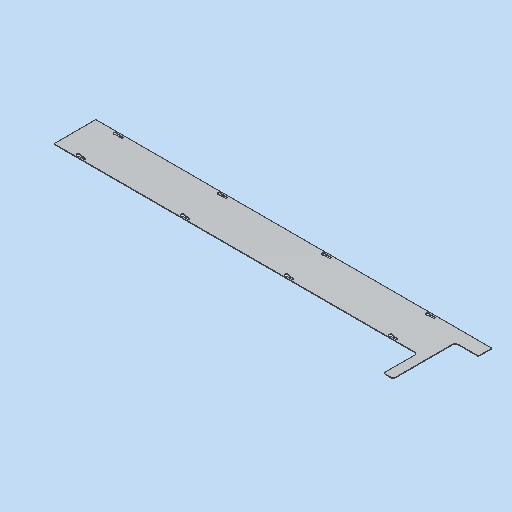
# Autodesk Inventor part: MM0948AN170_G01_102
Saved by Autodesk Inventor 2023.3 (Build 273359000, 359)
## iProperties
Part Number: MM0948AN170_G01_102
Material: 3.3535 AlMg3 - AW 5754 (Blech)
Description: =<RBPARTNOTITLE2>
Document SubType Name: Blech
Designer: Benutzer
Mass: 971.716 g
Surface Area: 3674.69 cm^2
Volume: 360.028 cm^3
Density: 2.699 g/cm^3
Sheet Metal Rule: Standard_mm
Appearance: Aluminium AnP
Vendor: ASW
Created: 2023-03-23
RBCHANGEDESCRIPTION1: Erstfreigabe
RBCHANGENO1: 00
RBDOCUMENTTYPE: DRF
RBDOCUMENTVERSION: 00
RBDRAWINGMAINSCALE: 1:1
RBDRAWINGMISSINGSPEC: --
RBDRAWINGVOLUME: --
RBDSV1: 0850
RBGBDETAILS: 43274
RBGBEDGESIN1: +0,5
RBGBEDGESIN2: +0,2
RBGBEDGESOUT1: -0,3
RBGBEDGESOUT2: -0,1
RBMATERIAL: =<Material>
RBMATMEETS: --
RBMATNO: =<Part Number>
RBORGUNITRESPONSIBLE1: AnP/TEF1
RBPARTMADEOF: 2 x 253 x 1324 (FM)
RBPARTNO: SIEHE MNR
RBPARTNOTITLE1: manufactured part
RBPARTNOTITLE2: Anfertigungsteil
RBPARTSAFETYINDICATOR: --
RBSURFACE: anodised grey
RBSURFACE2: eloxiert E6/EV1 aluminiumfarbig
RBZEDGESNORM: ISO13715:2002-06
RBZGENDIMCLASS: m
RBZGENDIMNORM: ISO 2768-1:1989-11
RBZGENGEOCLASS: H
RBZGENGEONORM: ISO 2768-2:1989-11
RBZSURFACENORM: ISO13D2:2002-02
RBZTOLERANCENORM: ISO 14405-1:2010-12
AnP_Material: =<Material>
AnP_TemplVers: 20190222
AnP_Kategorie: 1
MaxAbmaße: 2 x 253 x 1324 (FM)
AnP_Kommentar_aktuell: =<Comments>
AnP_Material_aktuell: =<Material>
Author: FH/Wi
Keywords: =<RBPARTMADEOF>
Comments: =<RBSURFACE2>
Revision Number: 01
Autodesk Inventor part; units mm, degrees
ref_plane "YZ Plane" through (0, 0, 0) normal (1, 0, 0) x (0, 1, 0)
ref_plane "XZ Plane" through (0, 0, 0) normal (0, 1, 0) x (-1, 0, 0)
ref_plane "XY Plane" through (0, 0, 0) normal (0, 0, 1) x (1, 0, 0)
sketch "Skizze1" plane through (0, 0, 0) normal (0, 0, 1) x (1, 0, 0)
  line L0 (0, 0) -> (1300, 0)
  line L1 (1300, 0) -> (1300, 140)
  line L2 (1300, 140) -> (0, 140)
  line L3 (0, 140) -> (0, 0)
  dimension "d0" = 1300
  dimension "d1" = 140
  constraints: 8 end point, 2 parallel, 1 horizontal, 1 perpendicular
  measures "d0" distance of L2.end L1.end
  measures "d1" distance of L1.end L0.end
extrude "Extrusion1" add sketch "Skizze1" along normal blind 2
sketch "Skizze5" plane through (1300, 0, 0) normal (1, 0, 0) x (0, 0, -1)
  line L0 (0, 0) -> (0, 140) projected
  line L1 (0, 140) -> (-2, 140) projected
  line L2 (-2, 0) -> (-2, 140) projected
  line L3 (0, 0) -> (-2, 0) projected
  point P0 (0, 0)
extrude "Extrusion4" add sketch "Skizze5" along normal blind 24
sketch "Skizze7" plane through (0, 0, 0) normal (0, -1, 0) x (1, 0, 0)
  line L0 (0, 0) -> (1324, 0) projected
  line L1 (1324, 2) -> (1324, 0) projected
  line L2 (0, 2) -> (1324, 2) projected
  line L3 (0, 0) -> (0, 2) projected
  line L4 (1215, 2) -> (1324, 2)
  line L5 (1324, 2) -> (1324, 0)
  line L6 (1324, 0) -> (1215, 0)
  line L7 (1215, 0) -> (1215, 2)
  dimension "d44" = 109
  constraints: 8 end point, 2 parallel, 1 horizontal, 1 perpendicular
  measures "d44" distance between parallel lines of L7 L1
extrude "Extrusion6" add sketch "Skizze7" along normal blind 113 contours L7 L2 L1 L0
sketch "Skizze9" plane through (0, 0, 2) normal (0, 0, 1) x (1, 0, 0)
  line L0 (1324, 95) -> (1247, 95)
  line L1 (1247, 95) -> (1247, -113)
  line L2 (1247, -113) -> (1324, -113)
  line L3 (1324, -113) -> (1324, 95)
  line L4 (1215, 0) -> (1215, -113) projected
  point P0 (0, 0)
  dimension "d68" = 32
  dimension "d69" = 208
  constraints: 8 end point, 2 parallel, 1 coincident, 1 horizontal, 1 perpendicular
  measures "d68" distance between parallel lines of L1 L4
  measures "d69" distance of L2.end L0.start
extrude "Ausklinkung1" cut sketch "Skizze9" against normal blind 2
fillet "Rundung1" radius 5 2 edges at (1215, -113, 1) (1247, -113, 1)
fillet "Rundung2" radius 10 2 edges at (1215, 0, 1) (1247, 95, 1)
sketch "Skizze8" plane through (0, 0, 2) normal (0, 0, 1) x (1, 0, 0)
  line L0 (73, 132) -> (95, 132) construction
  line L1 (73, 129) -> (95, 129)
  line L2 (95, 135) -> (73, 135)
  arc A0 (73, 135) -> (73, 129) centre (73, 132) ccw
  arc A1 (95, 129) -> (95, 135) centre (95, 132) ccw
  line L3 (73, 8) -> (95, 8) construction
  line L4 (73, 5) -> (95, 5)
  line L5 (95, 11) -> (73, 11)
  arc A2 (73, 11) -> (73, 5) centre (73, 8) ccw
  arc A3 (95, 5) -> (95, 11) centre (95, 8) ccw
  line L6 (0, 140) -> (1324, 140) projected
  line L7 (0, 140) -> (0, 0) projected
  circle A4 centre (73, 132) radius 5.5
  circle A5 centre (73, 8) radius 5.5
  point P0 (84, 132)
  point P1 (84, 8)
  dimension "d49" = 22
  dimension "d50" = 6
  dimension "d51" = 22
  dimension "d52" = 6
  dimension "d55" = 124
  dimension "d56" = 8
  dimension "d65" = 84
  dimension "d66" = 11
  dimension "d67" = 11
  constraints: 16 end point, 8 point on circle, 8 tangent, 6 centre point, 3 parallel, 2 coincident, 2 midpoint, 1 horizontal, 1 vertical alignment
  measures "d49" distance of L0.start L0.end
  measures "d50" diameter of A1
  measures "d51" distance of L3.start L3.end
  measures "d52" diameter of A3
  measures "d55" distance of point (84, 8) point (84, 132)
  measures "d56" distance from line of L6 point (84, 132)
  measures "d65" distance from line of point (84, 132) L7
  measures "d66" diameter of A4
  measures "d67" diameter of A5
extrude "Extrusion7" cut sketch "Skizze8" against normal blind 10
pattern_linear "Rechteckige Anordnung3" count 5 spacing 348 along (1, 0, 0) of "Extrusion7"
equation "\"d71\" = Stärke"
equation "\"Biegeradius\" = Stärke"
equation "\"BreiteBiegungsfreistellung\" = Stärke"
equation "\"TiefeBiegungsfreistellung\" = 0.5 * Stärke"
equation "\"GrößeEckenfreistellung\" = 4 * Stärke"
equation "\"MinimalRest\" = 2 * Stärke"
equation "\"Übergangsradius\" = Biegeradius"
equation "\"JacobiRadiusGröße\" = Biegeradius"
equation "\"Abstandsgröße\" = Stärke"
equation "\"d70\" = Stärke"
equation "\"Stärke\" = 2"
